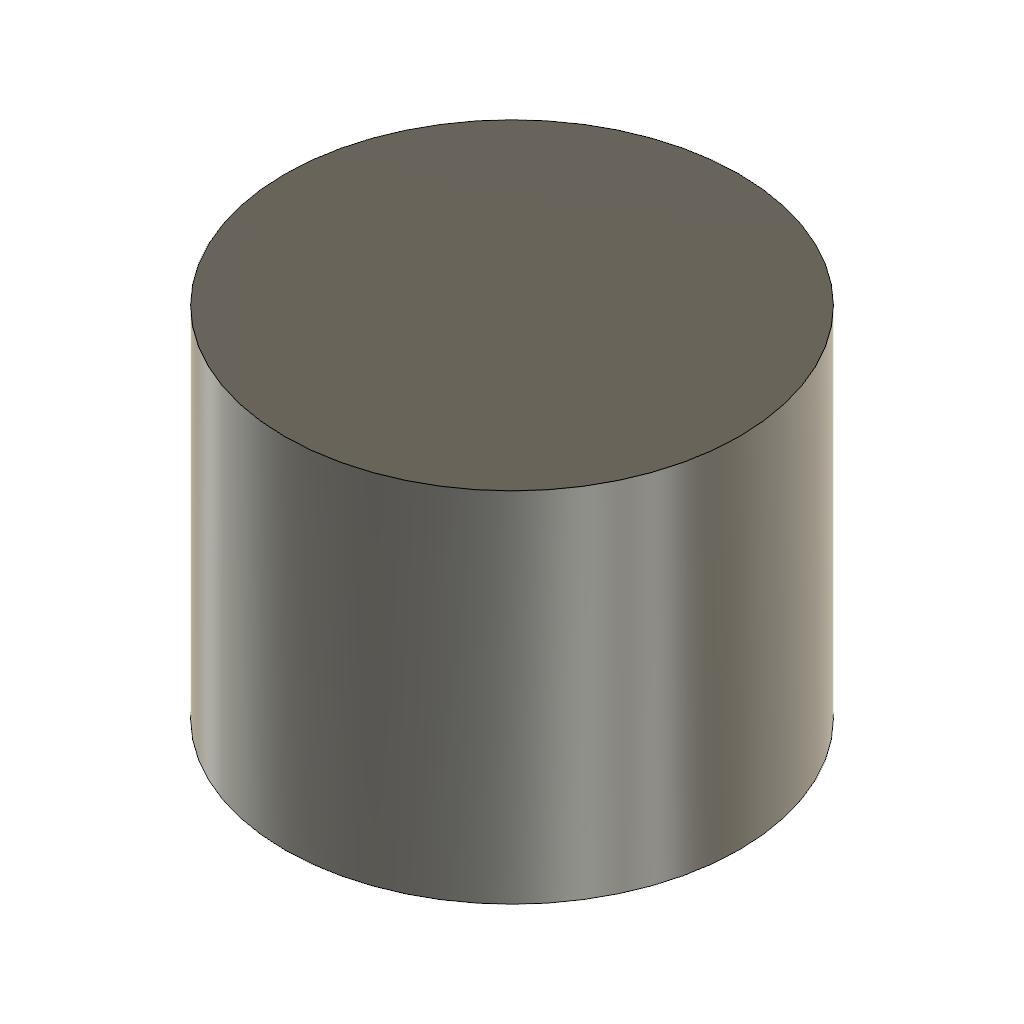
vendor_authored_extrusion (Autodesk Fusion 360 design; units mm, degrees)
Autodesk Fusion 360 part; units mm, degrees
sketch "Native On Authored Document" plane through (0, 0, 0) normal (0, 0, 1) x (1, 0, 0)
  circle A0 centre (0, 0) radius 20
extrude "Extrude1" add sketch "Native On Authored Document" along normal blind 31.5
equation "authoredLength = 31.5 mm" comment "Independently authored semantic parameter"
equation "d2 = authoredLength"
